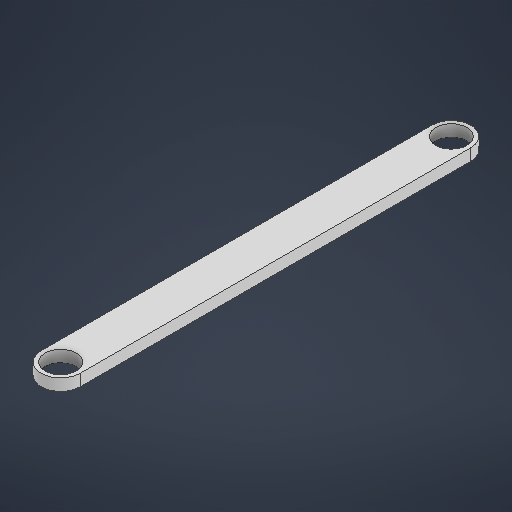
# Autodesk Inventor part: cuck_link
Saved by Autodesk Inventor 2027.1 (Build 311270010, 270A)
## iProperties
Created: 2026-11-04
Part Number: cuck_link
Material: Ogólny
Document SubType Name: Modeling
Designer: User
Density: 1 g/cm^3
Appearance: Domyślna
Author: User
Autodesk Inventor part; units mm, degrees
ref_plane "YZ Plane" through (0, 0, 0) normal (1, 0, 0) x (0, 1, 0)
ref_plane "XZ Plane" through (0, 0, 0) normal (0, 1, 0) x (-1, 0, 0)
ref_plane "XY Plane" through (0, 0, 0) normal (0, 0, 1) x (1, 0, 0)
sketch "Szkic1" plane through (0, 0, 0) normal (0, 1, 0) x (-1, 0, 0)
  circle A0 centre (0, 0) radius 4
  circle A1 centre (0, 0) radius 5
  line L0 (5, 0) -> (5, -50)
  line L1 (5, 0) -> (55, 0) construction
  line L2 (-5, 0) -> (-5, -50)
  line L3 (-5, 0) -> (45, 0) construction
  line L4 (5, -50) -> (-5, -50) construction
  circle A2 centre (0, -100) radius 4
  circle A3 centre (0, -100) radius 5
  line L5 (5, -100) -> (5, -50)
  line L6 (5, -100) -> (55, -100) construction
  line L7 (-5, -100) -> (-5, -50)
  line L8 (-5, -100) -> (45, -100) construction
  dimension "d0" = 8
  dimension "d1" = 10
  dimension "d2" = 50
  dimension "d3" = 90
  dimension "d4" = 50
  dimension "d5" = 90
  constraints: 18 end point, 7 symmetric about line, 4 centre point, 4 coincident, 4 point on circle, 2 horizontal, 2 perpendicular, 2 tangent, 2 vertical, 2 other
  measures "d0" diameter of A0
  measures "d1" diameter of A1
  measures "d2" distance of L0.start L0.end
  measures "d3" angle of L0 L1
  measures "d4" distance of L2.start L2.end
  measures "d5" angle of L2 L3
extrude "Wyciągnięcie proste1" add sketch "Szkic1" along normal blind 3
